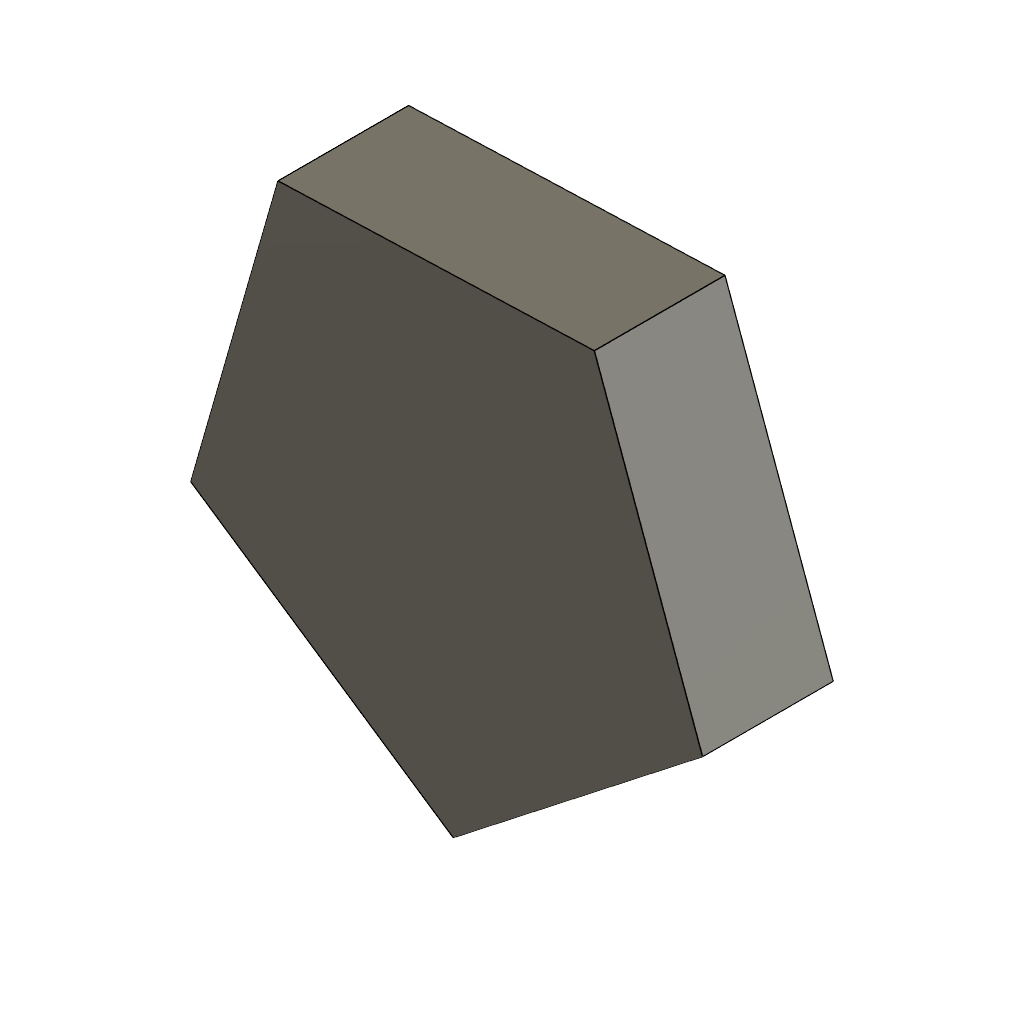
sk_polygon_circumscribed_pentagon (Autodesk Fusion 360 design; units mm, degrees)
part number: 2026-11-13-14-35-01-386
Autodesk Fusion 360 part; units mm, degrees
sketch "Sketch1" plane through (0, 0, 0) normal (0, 0, 1) x (1, 0, 0)
  line L0 (6.912, 10.2475) -> (-7.61, 9.7403)
  line L1 (-7.61, 9.7403) -> (-11.6152, -4.2276)
  line L2 (-11.6152, -4.2276) -> (0.4314, -12.3531)
  line L3 (0.4314, -12.3531) -> (11.8818, -3.4071)
  line L4 (11.8818, -3.4071) -> (6.912, 10.2475)
extrude "Extrude1" add sketch "Sketch1" along normal blind 6
